3DSCase (Autodesk Fusion 360 design; units mm, degrees)
Autodesk Fusion 360 part; units mm, degrees
sketch "Sketch1" plane through (0, 0, 0) normal (0, 0, 1) x (1, 0, 0)
  line L0 (16.5, -17.5) -> (-16.5, -17.5)
  line L1 (-16.5, -17.5) -> (-16.5, 17.5)
  line L2 (-16.5, 17.5) -> (16.5, 17.5)
  line L3 (16.5, 17.5) -> (16.5, -17.5)
  line L4 (17.5, -18.5) -> (-17.5, -18.5)
  line L5 (-17.5, -18.5) -> (-17.5, 18.5)
  line L6 (-17.5, 18.5) -> (17.5, 18.5)
  line L7 (17.5, 18.5) -> (17.5, -18.5)
  line L8 (16.5, 17.5) -> (18.5, 17.5)
  line L9 (18.5, 17.5) -> (18.5, 10.5)
  line L10 (18.5, 10.5) -> (16.5, 10.5)
  line L11 (16.5, 10.5) -> (16.5, 17.5)
  line L12 (16.5, 10.5) -> (16.5, 9.5)
  line L13 (16.5, 9.5) -> (19.5, 9.5)
  line L14 (19.5, 9.5) -> (19.5, 18.5)
  line L15 (19.5, 18.5) -> (16.5, 18.5)
  line L16 (16.5, 18.5) -> (16.5, 9.5)
  dimension "d1" = 35
  dimension "d2" = 33
  dimension "d3" = 35
  dimension "d4" = 37
  dimension "d20" = 2
  dimension "d21" = 7
  dimension "d22" = 1
  dimension "d23" = 9
  dimension "d24" = 3
  constraint perpendicular L0 L1
  constraint parallel L0 L2
  constraint parallel L1 L3
  constraint horizontal L0
  constraint perpendicular L4 L5
  constraint parallel L4 L6
  constraint parallel L5 L7
  constraint horizontal L4
  constraint horizontal L8
  constraint vertical L9
  constraint horizontal L10
  constraint vertical L11
  constraint vertical L12
  constraint horizontal L13
  constraint vertical L14
  constraint horizontal L15
  constraint vertical L16
  measures "d1" distance of L0.end L1.end
  measures "d2" distance of L1.end L2.end
  measures "d3" distance of L5.end L6.end
  measures "d4" distance of L4.end L5.end
  measures "d20" distance of L2.end L8.end
  measures "d21" distance of L2.end L10.end
  measures "d22" distance of L10.end L12.end
  measures "d23" distance of L12.end L15.end
  measures "d24" distance of L12.end L13.end
extrude "Extrude1" add sketch "Sketch1" along normal blind 2 contours L0 L1 L2 L3 L4 L5 L6 L7 L13 L16 | L0 L1 L2 L3 L11 L12 L16 | L3 L7 L10 L12 L13 L16 | L3 L7 L8 L10 L11 L16 | L6 L7 L8 L15 L16
sketch "Sketch2" plane through (0, 0, 2) normal (0, 0, 1) x (1, 0, 0)
  line L0 (17.5, 18.5) -> (-17.5, 18.5)
  line L1 (-17.5, 18.5) -> (-17.5, -18.5)
  line L2 (-17.5, -18.5) -> (17.5, -18.5)
  line L3 (17.5, -18.5) -> (17.5, 18.5)
  line L4 (16.5, -17.5) -> (-16.5, -17.5)
  line L5 (-16.5, -17.5) -> (-16.5, 17.5)
  line L6 (-16.5, 17.5) -> (16.5, 17.5)
  line L7 (16.5, 17.5) -> (16.5, -17.5)
  point P0 (16.5, -17.5)
  constraint perpendicular L4 L5
  constraint parallel L4 L6
  constraint parallel L5 L7
  constraint horizontal L4
  constraint coincident P0 L4.start
extrude "Extrude2" add sketch "Sketch2" along normal blind 4
sketch "Sketch3" plane through (0, -17.5, 0) normal (0, 1, 0) x (-1, 0, 0)
  line L0 (-16.5, 2) -> (16.5, 2)
  line L1 (16.5, 2) -> (16.5, 6)
  line L2 (16.5, 6) -> (-16.5, 6)
  line L3 (-16.5, 6) -> (-16.5, 2)
  line L4 (16.5, 6) -> (16.5, 5.8)
  line L5 (16.5, 6) -> (-16.5, 6)
  line L6 (-16.5, 6) -> (-16.5, 5.8)
  line L7 (-16.5, 5.8) -> (16.5, 5.8)
  line L8 (16.5, 5.8) -> (16.5, 6)
  dimension "d9" = 0.2
  dimension "d10" = 33
  dimension "d11" = 0.2
  constraint coincident L1.end L2.start
  constraint vertical L4
  constraint horizontal L5
  constraint vertical L6
  constraint horizontal L7
  constraint vertical L8
  measures "d9" distance of L1.end L4.end
  measures "d10" distance of L1.end L2.end
  measures "d11" distance of L1.end L4.end
extrude "Extrude3" add sketch "Sketch3" along normal blind 0.5 contours L1 L2 L3 L4 L5 L6 L7 L8
sketch "Sketch4" plane through (0, 18.5, 0) normal (0, 1, 0) x (-1, 0, 0)
  line L0 (-17.5, 0) -> (17.5, 0)
  line L1 (17.5, 0) -> (17.5, 6)
  line L2 (17.5, 6) -> (-17.5, 6)
  line L3 (-17.5, 6) -> (-17.5, 0)
  circle A0 centre (0, 6) radius 4
  dimension "d15" = 8
  constraint midpoint L2 A0.centre
  measures "d15" diameter of A0
extrude "Extrude4" cut sketch "Sketch4" against normal up to surface (1 mm away) contours L2 A0 picked at (-0.7259, 4.4523)
extrude "Extrude5" add sketch "Sketch1" along normal blind 2 contours L7 L8 L9 L10 L13 L14 L15 | L7 L8 L9 L10
extrude "Extrude6" add sketch "Sketch1" along normal blind 6 contours L7 L8 L9 L10 L13 L14 L15
extrude "Extrude7" cut sketch "Sketch1" along normal blind 6 and the other way blind -2 contours L3 L7 L8 L10 L11 L16
move_face "OffsetFaces1" offset 0.2 1 faces at (19.5, 12.5, 2)
move_face "OffsetFaces2" offset 0.2 1 faces at (18.2333, 9.5, 2)
move_face "OffsetFaces3" offset 0.2 4 faces at (17.5, 0.0333, 2) (5.8333, -18.5, 2) (-17.5, -6.1667, 4) (14.4074, 18.5, 3.607)
fillet "Fillet4" [suppressed]
fillet "Fillet5" [suppressed]
fillet "Fillet6" [suppressed]
fillet "Fillet7" [suppressed]
fillet "Fillet8" [suppressed]
fillet "Fillet9" [suppressed]
